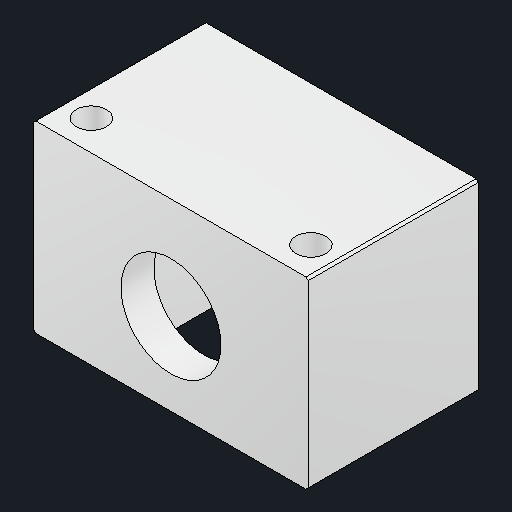
# Autodesk Inventor part: monotaro-TR16-nut-holder
Saved by Autodesk Inventor 2027.1 (Build 311270010, 270A)
## iProperties
Created: 2026-11-14
Part Number: monotaro-TR16-nut-holder
Material: Aluminum 6061
Document SubType Name: Modeling
Designer: queezz
Density: 2.7 g/cm^3
Appearance: Aluminum - Flat
Author: queezz
Autodesk Inventor part; units mm, degrees
sketch "Sketch1" plane through (0, 0, 0) normal (0, 0, 1) x (1, 0, 0)
  line L0 (-25, -23.5) -> (25, -23.5)
  line L1 (25, -23.5) -> (25, 18.5)
  line L2 (25, 18.5) -> (-25, 18.5)
  line L3 (-25, 18.5) -> (-25, -23.5)
  constraints: 8 end point, 2 parallel, 1 horizontal, 1 perpendicular
extrude "Housing blank" add sketch "Sketch1" along normal blind 31
ref_plane "Work Plane1" through (0, 0, 0) normal (0, 0, 1) x (1, 0, 0)
sketch "Screw passage" plane through (0, 0, 0) normal (0, 0, 1) x (1, 0, 0)
  circle A0 centre (0, 0) radius 9.1
  constraints: 1 centre point
extrude "Screw clearance" cut sketch "Screw passage" along normal blind 31
ref_plane "Work Plane2" through (0, 0, 0) normal (0, 0, 1) x (1, 0, 0)
sketch "Round nut seat" plane through (0, 0, 0) normal (0, 0, 1) x (1, 0, 0)
  circle A0 centre (0, 0) radius 15.1
  constraints: 1 centre point
extrude "25 mm nut pocket and axial shoulder" [suppressed]
ref_plane "Work Plane3" through (0, 0, 0) normal (0, 0, 1) x (1, 0, 0)
sketch "Mount clearance" plane through (0, 0, 0) normal (0, 0, 1) x (1, 0, 0)
  circle A0 centre (-19.5, -12.5) radius 1.65
  circle A1 centre (-19.5, 12.5) radius 1.65
  circle A2 centre (19.5, -12.5) radius 1.65
  circle A3 centre (19.5, 12.5) radius 1.65
  constraints: 4 centre point
extrude "M4 keeper tap pilots" [suppressed]
ref_plane "Work Plane4" through (0, 0, 0) normal (0, 0, 1) x (1, 0, 0)
sketch "Trim to underside of rear foot" plane through (0, 0, 0) normal (0, 0, 1) x (1, 0, 0)
  line L0 (-26, -35) -> (26, -35)
  line L1 (26, -35) -> (26, -15)
  line L2 (26, -15) -> (-26, -15)
  line L3 (-26, -15) -> (-26, -35)
  constraints: 8 end point, 2 parallel, 1 horizontal, 1 perpendicular
extrude "Foot mating face" cut sketch "Trim to underside of rear foot" along normal blind 32
ref_plane "Work Plane5" through (0, 20, 0) normal (0, 1, 0) x (-1, 0, 0)
sketch "Sketch6" plane through (0, 20, 0) normal (0, 1, 0) x (-1, 0, 0)
  circle A0 centre (20, 17.5) radius 2.75
  circle A1 centre (-20, 17.5) radius 2.75
  constraints: 2 centre point
extrude "Two vertical M5 housing bolt clears" [suppressed]
ref_plane "Work Plane6" through (-25, 0, 12.5) normal (1, 0, 0) x (0, 1, 0)
sketch "Sketch7" plane through (-25, 0, 12.5) normal (1, 0, 0) x (0, 1, 0)
  circle A0 centre (0, 0) radius 2.1
  constraints: 1 centre point
extrude "M5 dog screw anti-rotation pilot" [suppressed]
sketch "Revised keeper pattern with head clearance" plane through (0, 0, 0) normal (0, 0, 1) x (1, 0, 0)
  circle A0 centre (-19.5, -12.5) radius 1.65
  circle A1 centre (-19.5, -6) radius 1.65
  circle A2 centre (19.5, -12.5) radius 1.65
  circle A3 centre (19.5, -6) radius 1.65
  constraints: 4 centre point
extrude "Revised keeper screw holes" [suppressed]
ref_plane "Work Plane7" through (0, -20, 0) normal (0, -1, 0) x (1, 0, 0)
sketch "Sketch9" plane through (0, -20, 0) normal (0, -1, 0) x (1, 0, 0)
  circle A0 centre (-20, 17.5) radius 2.75
  circle A1 centre (20, 17.5) radius 2.75
  constraints: 2 centre point
extrude "M5 vertical clearances at 40 mm centers" [suppressed]
sketch "Sketch10" plane through (0, 0, 0) normal (0, 0, 1) x (1, 0, 0)
  circle A0 centre (-19.5, -14.2) radius 1.65
  circle A1 centre (-19.5, -6) radius 1.65
  circle A2 centre (19.5, -14.2) radius 1.65
  circle A3 centre (19.5, -6) radius 1.65
  constraints: 4 centre point
extrude "M4 keeper pattern at 8.2 mm row spacing" [suppressed]
sketch "Matched M4 keeper hole positions" plane through (0, 0, 0) normal (0, 0, 1) x (1, 0, 0)
  circle A0 centre (-19, -6) radius 1.65
  circle A1 centre (-19, 12.5) radius 1.65
  circle A2 centre (19, -6) radius 1.65
  circle A3 centre (19, 12.5) radius 1.65
  constraints: 4 centre point
extrude "Four enclosed keeper holes" cut sketch "Matched M4 keeper hole positions" along normal blind 10
ref_plane "Work Plane8" through (0, -24, 0) normal (0, -1, 0) x (1, 0, 0)
sketch "Sketch12" plane through (0, -24, 0) normal (0, -1, 0) x (1, 0, 0)
  circle A0 centre (-20, 25.5) radius 2.75
  circle A1 centre (20, 25.5) radius 2.75
  constraints: 2 centre point
extrude "Full depth M5 housing bolt bores" cut sketch "Sketch12" against normal blind 45
chamfer "C0.4 outside perimeter" [suppressed]
ref_plane "Work Plane9" through (0, 0, 0) normal (0, 0, 1) x (1, 0, 0)
ref_plane "Work Plane10" through (0, 0, 0) normal (0, 0, 1) x (1, 0, 0)
sketch "Open saddle profile, R3 cutter corners" plane through (0, 0, 0) normal (0, 0, 1) x (1, 0, 0)
  line L0 (-12.6, -16) -> (12.6, -16)
  line L1 (12.6, -16) -> (12.6, 12.2)
  arc A0 (12.6, 12.2) -> (9.6, 15.2) centre (9.6, 12.2) ccw
  line L2 (9.6, 15.2) -> (-9.6, 15.2)
  arc A1 (-9.6, 15.2) -> (-12.6, 12.2) centre (-9.6, 12.2) ccw
  line L3 (-12.6, 12.2) -> (-12.6, -16)
  constraints: 8 end point, 4 point on circle, 2 centre point
extrude "Open nut saddle with 6 mm axial shoulder" cut sketch "Open saddle profile, R3 cutter corners" along normal blind 25
chamfer "C0.4 on four outer lengthwise edges" distance 0.4 angle 45 4 edges at (25, -15, 15.5) (-25, -15, 15.5) (-25, 18.5, 15.5) (25, 18.5, 15.5)
body "Solid1"
